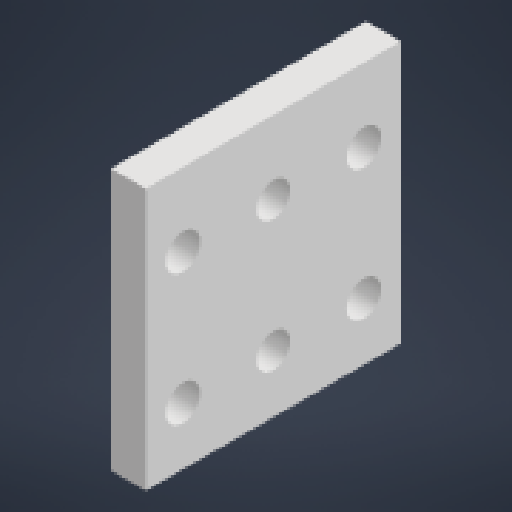
# Autodesk Inventor part: soporteCorrederas
Saved by Autodesk Inventor 2027.1 (Build 311270010, 270A)
## iProperties
Created: 2026-11-02
Part Number: soporteCorrederas
Material: Genérico
Document SubType Name: Modeling
Designer: MANGEL
Density: 1 g/cm^3
Appearance: Valor por defecto
Author: MANGEL
Autodesk Inventor part; units mm, degrees
ref_plane "YZ Plane" through (0, 0, 0) normal (1, 0, 0) x (0, 1, 0)
ref_plane "XZ Plane" through (0, 0, 0) normal (0, 1, 0) x (-1, 0, 0)
ref_plane "XY Plane" through (0, 0, 0) normal (0, 0, 1) x (1, 0, 0)
sketch "Boceto1" plane through (0, 0, 0) normal (1, 0, 0) x (0, 1, 0)
  line L0 (-60, 58.5) -> (60, 58.5)
  line L1 (60, 58.5) -> (60, -58.5)
  line L2 (60, -58.5) -> (-60, -58.5)
  line L3 (-60, -58.5) -> (-60, 58.5)
  line L4 (-60, 58.5) -> (60, -58.5) construction
  line L5 (60, 58.5) -> (-60, -58.5) construction
  point P0 (0, 0)
  dimension "d0" = 117
  dimension "d1" = 120
  constraints: 12 end point, 2 midpoint, 2 parallel, 1 horizontal, 1 perpendicular
  measures "d0" distance of L0.end L1.end
  measures "d1" distance of L0.start L0.end
extrude "Extrusión1" add sketch "Boceto1" along normal blind 16
sketch "Boceto2" plane through (16, 0, 0) normal (1, 0, 0) x (0, 0, -1)
  circle A0 centre (-41.5, 26.4) radius 8
  line L0 (58.5, 60) -> (-58.5, 60) projected
  circle A1 centre (0, 26.4) radius 7.75
  line L1 (0, 60) -> (0, 0) construction
  line L2 (-58.5, 60) -> (-58.5, -60) projected
  line L3 (58.5, -60) -> (58.5, 60) projected
  circle A2 centre (41.5, 26.4) radius 8
  circle A3 centre (-41.5, -33.6) radius 8
  circle A4 centre (0, -33.6) radius 7.75
  circle A5 centre (41.5, -33.6) radius 8
  point P0 (0, 30)
  point P1 (0, 60)
  dimension "d4" = 16
  dimension "d5" = 33.6
  dimension "d6" = 17
  dimension "d7" = 15.5
  dimension "d9" = 16
  dimension "d10" = 15.5
  dimension "d11" = 60
  dimension "d15" = 41.5
  constraints: 6 centre point, 3 midpoint, 3 vertical alignment, 2 end point, 2 horizontal alignment, 2 symmetric about line, 2 other
  measures "d4" diameter of A0
  measures "d5" distance from line of L0 A0.centre
  measures "d6" distance from line of L2 A0.centre
  measures "d7" diameter of A1
  measures "d9" diameter of A3
  measures "d10" diameter of A4
  measures "d11" distance of A0.centre A3.centre
  measures "d15" distance of A1.centre A0.centre
extrude "Extrusión2" cut sketch "Boceto2" against normal blind 60
equation "\"d12\" = d11"
